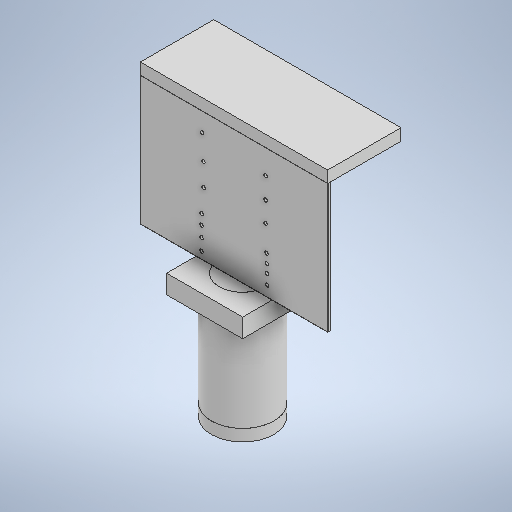
# Autodesk Inventor part: 06_coonector_plus_02mm
Saved by Autodesk Inventor 2025.3 (Build 293356000, 356)
## iProperties
Created: 2026-10-17
Part Number: 06_coonector_plus_02mm
Material: Generisch
Document SubType Name: Modeling
Designer: v.ivko
Density: 1 g/cm^3
Appearance: Vorgabe
Author: v.ivko
Autodesk Inventor part; units mm, degrees
ref_plane "YZ Plane" through (0, 0, 0) normal (1, 0, 0) x (0, 1, 0)
ref_plane "XZ Plane" through (0, 0, 0) normal (0, 1, 0) x (-1, 0, 0)
ref_plane "XY Plane" through (0, 0, 0) normal (0, 0, 1) x (1, 0, 0)
sketch "Skizze1" plane through (0, 0, 0) normal (0, 0, 1) x (1, 0, 0)
  line L0 (-8, -5.5) -> (8, -5.5)
  line L1 (8, -5.5) -> (8, 5.5)
  line L2 (8, 5.5) -> (-8, 5.5)
  line L3 (-8, 5.5) -> (-8, -5.5)
  line L4 (-8, -5.5) -> (8, 5.5) construction
  line L5 (8, -5.5) -> (-8, 5.5) construction
  point P0 (0, 0)
  dimension "d39" = 16
  dimension "d42" = 11
  constraints: 12 end point, 2 midpoint, 2 parallel, 1 horizontal, 1 perpendicular
  measures "d39" distance between parallel lines of L1 L3
  measures "d42" distance of L0.end L1.end
extrude "Extrusion1" add sketch "Skizze1" along normal blind 0.2
sketch "Skizze2" plane through (-8, -5.5, 0) normal (0, -1, 0) x (1, 0, 0)
  line L0 (8, 0) -> (8, -43.5363) construction
  line L1 (11.25, 2.75) -> (4.75, 2.75)
  line L2 (4.75, 2.75) -> (4.75, -3.75)
  line L3 (4.75, -3.75) -> (11.25, -3.75)
  line L4 (11.25, -3.75) -> (11.25, 2.75)
  line L5 (11.25, 2.75) -> (4.75, -3.75) construction
  line L6 (4.75, 2.75) -> (11.25, -3.75) construction
  line L7 (0, 0) -> (16, 0) projected
  circle A0 centre (8, -0.5) radius 2
  circle A1 centre (8, -0.5) radius 0.5 construction
  point P0 (11.25, 0)
  point P1 (4.75, 0)
  point P2 (6.0635, 0)
  point P3 (9.9365, 0)
  dimension "d2" = 6.5
  dimension "d3" = 6.5
  dimension "d4" = 0.5
  dimension "d27" = 4
  dimension "d30" = 1
  constraints: 14 end point, 2 centre point, 2 coincident, 2 midpoint, 2 parallel, 1 horizontal, 1 perpendicular, 1 point on line, 1 vertical
  measures "d2" distance of L2.end L3.end
  measures "d3" distance of L1.end L2.end
  measures "d4" distance from line of L7 point (8, -0.5)
  measures "d27" diameter of A0
  measures "d30" diameter of A1
extrude "Extrusion2" add sketch "Skizze2" along normal blind 1.6 separate body contours L4 L7 A0 L2 L1 | L4 L3 L2 L7 A0
sketch "Skizze3" plane through (-8, -7.1, 0) normal (0, -1, 0) x (1, 0, 0)
  circle A0 centre (8, -0.5) radius 2 projected
  circle A1 centre (8, -0.5) radius 2.675
  point P0 (8, 0)
  dimension "d28" = 5.35
  constraints: 1 centre point, 1 coincident
  measures "d28" diameter of A1
extrude "Extrusion3" add sketch "Skizze3" along normal blind 8 bodies 2
sketch "Skizze4" plane through (0, -15.1, -0.5) normal (0, -1, 0) x (1, 0, 0)
  circle A0 centre (0, 0) radius 0.5
  circle A1 centre (0, 0) radius 2 projected
  point P0 (0, 0.5)
  dimension "d29" = 1
  constraints: 1 centre point
  measures "d29" diameter of A0
extrude "Extrusion4" add sketch "Skizze4" against normal up to surface (9.6 mm away) separate body
sketch "Skizze5" plane through (0, -15.1, -0.5) normal (0, -1, 0) x (1, 0, 0)
  circle A0 centre (0, 0) radius 0.5
  point P0 (0, 0.5)
  dimension "d31" = 1
  constraints: 1 centre point
  measures "d31" diameter of A0
extrude "Extrusion5" add sketch "Skizze5" against normal up to surface (9.6 mm away) separate body
sketch "Skizze6" plane through (0, -5.5, -0.5) normal (0, 1, 0) x (1, 0, 0)
  circle A0 centre (0, 0) radius 0.5 projected
  point P0 (0, -0.5)
extrude "Extrusion6" add sketch "Skizze6" along normal blind 4 bodies 4
sketch "Skizze7" plane through (-8, -5.5, 0) normal (0, 1, 0) x (1, 0, 0)
  line L0 (4.75, 0.035) -> (5.75, 0.035)
  line L1 (5.75, 0.035) -> (5.75, 1.035)
  line L2 (5.75, 1.035) -> (4.75, 1.035)
  line L3 (4.75, 1.035) -> (4.75, 0.035)
  line L4 (4.75, 0.035) -> (5.75, 1.035) construction
  line L5 (5.75, 0.035) -> (4.75, 1.035) construction
  circle A0 centre (8, 0.5) radius 0.5 projected
  line L6 (8, 0.5) -> (8, 3.9078) construction
  line L7 (16, 0) -> (0, 0) projected
  line L8 (4.75, -2.75) -> (4.75, 3.75) projected
  line L9 (11.25, 0.035) -> (10.25, 0.035)
  line L10 (10.25, 0.035) -> (10.25, 1.035)
  line L11 (10.25, 1.035) -> (11.25, 1.035)
  line L12 (11.25, 1.035) -> (11.25, 0.035)
  point P0 (8, 0)
  point P1 (5.25, 0.535)
  dimension "d15" = 1
  dimension "d16" = 1
  dimension "d17" = 0.035
  constraints: 22 end point, 4 symmetric about line, 2 midpoint, 2 parallel, 1 collinear, 1 horizontal, 1 perpendicular, 1 vertical
  measures "d15" distance of L1.end L2.end
  measures "d16" distance of L2.end L0.start
  measures "d17" distance between parallel lines of L7 L0
extrude "Extrusion7" add sketch "Skizze7" along normal blind 4 contours L3 L2 L1 L0 | L9 L10 L11 L12 bodies 2
sketch "Skizze8" plane through (0, 0, 0) normal (0, 0, -1) x (-1, 0, 0)
  line L0 (0.5, 5.5) -> (-0.5, 5.5)
  line L1 (-0.5, 5.5) -> (-0.5, -5.5)
  line L2 (-0.5, -5.5) -> (0.5, -5.5)
  line L3 (0.5, -5.5) -> (0.5, 5.5)
  line L4 (0.5, 5.5) -> (-0.5, -5.5) construction
  line L5 (-0.5, 5.5) -> (0.5, -5.5) construction
  line L6 (8, -5.5) -> (-8, -5.5) projected
  line L7 (8, 5.5) -> (8, -5.5) projected
  line L8 (-8, -5.5) -> (-8, 5.5) projected
  line L9 (0, 0) -> (0, -24.5211) construction
  line L10 (0, 0) -> (0, -5.5) construction
  line L11 (-0.9, -5.5) -> (-8, -5.5)
  line L12 (-8, -5.5) -> (-8, 5.5)
  line L13 (-8, 5.5) -> (-0.9, 5.5)
  line L14 (-0.9, 5.5) -> (-0.9, -5.5)
  line L15 (0.9, -5.5) -> (8, -5.5)
  line L16 (8, -5.5) -> (8, 5.5)
  line L17 (8, 5.5) -> (0.9, 5.5)
  line L18 (0.9, 5.5) -> (0.9, -5.5)
  dimension "d20" = 1
  dimension "d21" = 11
  constraints: 32 end point, 6 parallel, 3 collinear, 3 horizontal, 3 midpoint, 3 perpendicular, 1 symmetric about line, 1 vertical
  measures "d20" distance between parallel lines of L1 L3
  measures "d21" distance of L0.end L1.end
extrude "Extrusion8" add sketch "Skizze8" along normal blind 0.035 separate body
sketch "Skizze9" plane through (0, 0, 0.2) normal (0, 0, 1) x (1, 0, 0)
  line L0 (8, -5.5) -> (8, 5.5) projected
  line L1 (8, 5.5) -> (-8, 5.5) projected
  line L2 (-8, 5.5) -> (-8, -5.5) projected
  line L3 (-8, -5.5) -> (8, -5.5) projected
  point P0 (0, 0)
extrude "Extrusion9" add sketch "Skizze9" along normal blind 0.035 separate body
sketch "Skizze10" plane through (0, -1.5, -0.5) normal (0, 1, 0) x (1, 0, 0)
  circle A0 centre (0, 0) radius 0.5 projected
  line L0 (0.5, -0.465) -> (-0.5, -0.465) projected
  line L1 (-0.5, 0) -> (0.5, 0)
  line L2 (0.5, 0) -> (0.5, -0.465)
  line L3 (0.5, -0.465) -> (-0.5, -0.465)
  line L4 (-0.5, -0.465) -> (-0.5, 0)
  line L5 (0.5, 0) -> (0.5, 0.1708) construction
  point P0 (0, -0.5)
  constraints: 10 end point, 2 parallel, 2 point on circle, 1 collinear, 1 horizontal, 1 perpendicular, 1 point on line, 1 tangent, 1 vertical
extrude "Extrusion10" add sketch "Skizze10" against normal blind 2 separate body contours L2 L0 A0 | A0 L0 L1 | A0 L0 L4
sketch "Skizze11" plane through (0, -15.1, -0.5) normal (0, -1, 0) x (1, 0, 0)
  line L0 (-0.5, 0) -> (0.5, 0) projected
  circle A0 centre (0, 0) radius 2.675
  point P0 (0, 0.5)
  constraints: 1 centre point, 1 midpoint
extrude "Extrusion11" add sketch "Skizze11" along normal blind 1 separate body
sketch "Skizze13" plane through (0, 0, -0.035) normal (0, 0, -1) x (-1, 0, 0)
  circle A0 centre (-2.7665, -2.2662) radius 0.15
  circle A1 centre (-2.7944, -3.7426) radius 0.15
  circle A2 centre (-2.7944, -3.0462) radius 0.15
  circle A3 centre (-2.8362, -4.6062) radius 0.15
  circle A4 centre (2.7771, -2.1162) radius 0.15
  circle A5 centre (2.7911, -3.8926) radius 0.15
  circle A6 centre (2.7911, -2.9766) radius 0.15
  circle A7 centre (2.7911, -4.8987) radius 0.15
  circle A8 centre (-2.6862, -0.1072) radius 0.15
  circle A9 centre (-2.6862, 1.6199) radius 0.15
  circle A10 centre (-2.6862, 3.4168) radius 0.15
  circle A11 centre (2.6133, -0.1101) radius 0.15
  circle A12 centre (2.6283, 1.8138) radius 0.15
  circle A13 centre (2.7336, 3.8881) radius 0.15
  dimension "d45" = 0.3
  dimension "d46" = 0.3
  dimension "d47" = 0.3
  dimension "d48" = 0.3
  dimension "d49" = 0.3
  dimension "d50" = 0.3
  dimension "d51" = 0.3
  dimension "d52" = 0.3
  dimension "d53" = 0.3
  dimension "d54" = 0.3
  dimension "d55" = 0.3
  dimension "d61" = 0.3
  dimension "d62" = 0.3
  dimension "d63" = 0.3
  constraints: 14 centre point
  measures "d45" diameter of A0
  measures "d46" diameter of A1
  measures "d47" diameter of A2
  measures "d48" diameter of A3
  measures "d49" diameter of A4
  measures "d50" diameter of A5
  measures "d51" diameter of A6
  measures "d52" diameter of A7
  measures "d53" diameter of A8
  measures "d54" diameter of A9
  measures "d55" diameter of A10
  measures "d61" diameter of A11
  measures "d62" diameter of A12
  measures "d63" diameter of A13
extrude "Extrusion13" cut sketch "Skizze13" against normal blind 10 bodies 5 1 6
sketch "Skizze15" plane through (-0.5, 5.5, 0) normal (0, 1, 0) x (1, 0, 0)
  line L0 (8.5, -0.235) -> (-7.5, -0.235) projected
  line L1 (-7.5, 0.035) -> (8.5, 0.035)
  line L2 (8.5, 0.035) -> (8.5, -0.235)
  line L3 (8.5, -0.235) -> (-7.5, -0.235)
  line L4 (-7.5, -0.235) -> (-7.5, 0.035)
  line L5 (-7.5, 0.035) -> (-0.4, 0.035) projected
  line L6 (-7.5, 0.035) -> (8.5, 0.035)
  line L7 (8.5, 0.035) -> (8.5, 6.035)
  line L8 (8.5, 6.035) -> (-7.5, 6.035)
  line L9 (-7.5, 6.035) -> (-7.5, 0.035)
  point P0 (0.5, 0)
  dimension "d72" = 6
  constraints: 16 end point, 4 parallel, 2 horizontal, 2 perpendicular, 1 collinear, 1 point on line
  measures "d72" distance of L8.end L5.start
extrude "Extrusion15" add sketch "Skizze15" along normal blind 1 separate body
